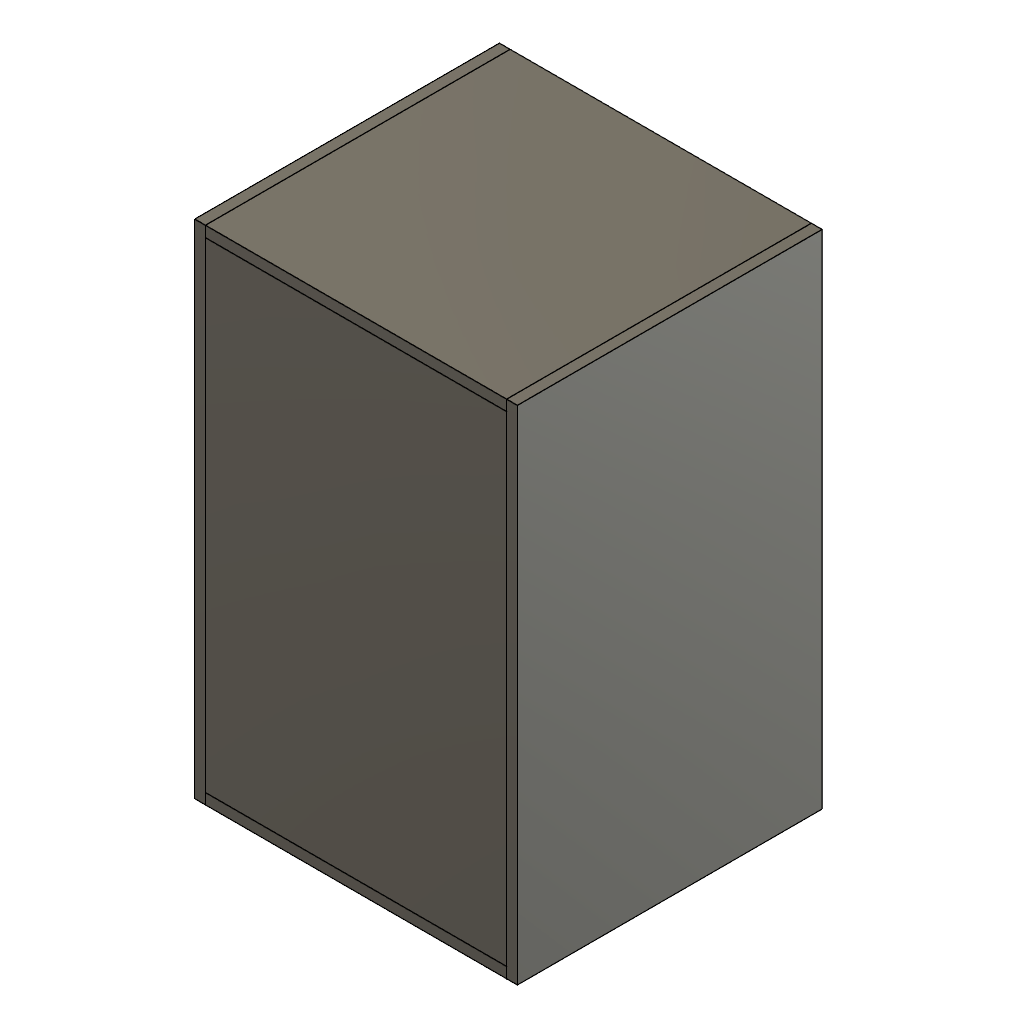
OPEN_LOUD_A0_E08 (Autodesk Fusion 360 design; units mm, degrees)
part number: 2026-11-10-20-48-52-947
part number: 2026-11-10-20-48-53-589
part number: 2026-11-10-20-48-53-740
part number: 2026-11-10-20-48-53-848
part number: 2026-11-10-20-48-53-970
part number: 2026-11-10-20-48-54-126
part number: 2026-11-10-20-48-54-325
part number: 2026-11-10-20-48-55-148
part number: 2026-11-10-20-49-07-626
part number: 2026-11-10-20-49-14-785
part number: 2026-11-10-20-49-16-073
part number: 2026-11-10-20-49-17-374
part number: 2026-11-10-20-49-18-731
part number: 2026-11-10-20-49-20-071
part number: 2026-11-10-20-49-21-540
part number: 2026-11-10-20-49-22-962
part number: 2026-11-10-20-49-24-387
part number: 2026-11-10-20-49-25-757
part number: 2026-11-10-20-49-30-177
part number: 2026-11-10-20-49-35-720
part number: 2026-11-10-20-49-37-012
Autodesk Fusion 360 part; units mm, degrees
(part 1 of 2)
ref_plane "Arbeitsebene1" through (0, 0, 0) normal (0, 0, 1) x (1, 0, 0) in component "Side_left"
sketch "Skizze1" plane through (0, 0, 0) normal (0, 0, 1) x (1, 0, 0) in component "Side_left"
  line L0 (0, 0) -> (12, 0)
  line L1 (12, 0) -> (12, 560)
  line L2 (12, 560) -> (0, 560)
  line L3 (0, 560) -> (0, 0)
  dimension "d76" = 12
  dimension "d77" = 560
  constraint horizontal L0
  constraint horizontal L2
  constraint vertical L1
  constraint vertical L3
  constraint coincident L0.start L3.end
  measures "d76" horizontal distance of L0.start L0.end
  measures "d77" vertical distance of L0.end L1.end
extrude "Side_left" add sketch "Skizze1" along normal blind 340 makes body 1 in component "Side_left"
ref_plane "Arbeitsebene1" through (0, 0, 0) normal (0, 0, 1) x (1, 0, 0) in component "Side_right"
sketch "Skizze1 (2)" plane through (0, 0, 0) normal (0, 0, 1) x (1, 0, 0) in component "Side_right"
  line L0 (348, 0) -> (360, 0)
  line L1 (360, 0) -> (360, 560)
  line L2 (360, 560) -> (348, 560)
  line L3 (348, 560) -> (348, 0)
  dimension "d82" = 348
  dimension "d83" = 12
  dimension "d84" = 560
  constraint horizontal L0
  constraint horizontal L2
  constraint vertical L1
  constraint vertical L3
  constraint horizontal origin L0.start
  measures "d82" horizontal distance of origin L0.start
  measures "d83" horizontal distance of L0.start L0.end
  measures "d84" vertical distance of L0.end L1.end
extrude "Side_right" add sketch "Skizze1 (2)" along normal blind 340 separate body makes body 2 in component "Side_right"
ref_plane "Arbeitsebene1" through (0, 0, 0) normal (0, 0, 1) x (1, 0, 0) in component "Bottom"
sketch "Skizze1 (3)" plane through (0, 0, 0) normal (0, 0, 1) x (1, 0, 0) in component "Bottom"
  line L0 (12, 0) -> (348, 0)
  line L1 (348, 0) -> (348, 12)
  line L2 (348, 12) -> (12, 12)
  line L3 (12, 12) -> (12, 0)
  dimension "d89" = 12
  dimension "d90" = 336
  dimension "d91" = 12
  constraint horizontal L0
  constraint horizontal L2
  constraint vertical L1
  constraint vertical L3
  constraint horizontal origin L0.start
  measures "d89" horizontal distance of origin L0.start
  measures "d90" horizontal distance of L0.start L0.end
  measures "d91" vertical distance of L0.end L1.end
extrude "Bottom" add sketch "Skizze1 (3)" along normal blind 340 separate body makes body 3 in component "Bottom"
ref_plane "Arbeitsebene1" through (0, 0, 0) normal (0, 0, 1) x (1, 0, 0) in component "Top"
sketch "Skizze1 (4)" plane through (0, 0, 0) normal (0, 0, 1) x (1, 0, 0) in component "Top"
  line L0 (12, 548) -> (348, 548)
  line L1 (348, 548) -> (348, 560)
  line L2 (348, 560) -> (12, 560)
  line L3 (12, 560) -> (12, 548)
  dimension "d96" = 12
  dimension "d97" = 548
  dimension "d98" = 336
  dimension "d99" = 12
  constraint horizontal L0
  constraint horizontal L2
  constraint vertical L1
  constraint vertical L3
  measures "d96" horizontal distance of origin L0.start
  measures "d97" vertical distance of origin L0.start
  measures "d98" horizontal distance of L0.start L0.end
  measures "d99" vertical distance of L0.end L1.end
extrude "Top" add sketch "Skizze1 (4)" along normal blind 340 separate body makes body 4 in component "Top"
ref_plane "Arbeitsebene1" through (0, 0, 0) normal (0, 0, 1) x (1, 0, 0) in component "Baffle"
sketch "Skizze1 (5)" plane through (0, 0, 0) normal (0, 0, 1) x (1, 0, 0) in component "Baffle"
  line L0 (12, 12) -> (348, 12)
  line L1 (348, 12) -> (348, 548)
  line L2 (348, 548) -> (12, 548)
  line L3 (12, 548) -> (12, 12)
  dimension "d104" = 12
  dimension "d105" = 12
  dimension "d106" = 336
  dimension "d107" = 536
  constraint horizontal L0
  constraint horizontal L2
  constraint vertical L1
  constraint vertical L3
  measures "d104" horizontal distance of origin L0.start
  measures "d105" vertical distance of origin L0.start
  measures "d106" horizontal distance of L0.start L0.end
  measures "d107" vertical distance of L0.end L1.end
extrude "Baffle" add sketch "Skizze1 (5)" along normal blind 12 separate body makes body 5 in component "Baffle"
ref_plane "Arbeitsebene1" through (0, 0, 328) normal (0, 0, 1) x (1, 0, 0) in component "Rear_removable"
sketch "Skizze1 (6)" plane through (0, 0, 328) normal (0, 0, 1) x (1, 0, 0) in component "Rear_removable"
  line L0 (12, 12) -> (348, 12)
  line L1 (348, 12) -> (348, 548)
  line L2 (348, 548) -> (12, 548)
  line L3 (12, 548) -> (12, 12)
  dimension "d112" = 12
  dimension "d113" = 12
  dimension "d114" = 336
  dimension "d115" = 536
  constraint horizontal L0
  constraint horizontal L2
  constraint vertical L1
  constraint vertical L3
  measures "d112" horizontal distance of origin L0.start
  measures "d113" vertical distance of origin L0.start
  measures "d114" horizontal distance of L0.start L0.end
  measures "d115" vertical distance of L0.end L1.end
extrude "Rear_removable" add sketch "Skizze1 (6)" along normal blind 12 separate body makes body 6 in component "Rear_removable"
ref_plane "Arbeitsebene2" through (0, 0, 0) normal (0, 0, 1) x (1, 0, 0) in component "Baffle"
sketch "Skizze2" plane through (0, 0, 0) normal (0, 0, 1) x (1, 0, 0) in component "Baffle"
  circle A0 centre (180, 260) radius 117.15
  dimension "d120" = 180
  dimension "d121" = 260
  dimension "d122" = 234.3
  measures "d120" horizontal distance of origin A0.centre
  measures "d121" vertical distance of origin A0.centre
  measures "d122" diameter of A0
extrude "LF_cut" cut sketch "Skizze2" along normal blind 12 bodies 5 in component "Baffle"
ref_plane "Arbeitsebene3" through (0, 0, 0) normal (0, 0, 1) x (1, 0, 0) in component "Baffle"
sketch "Skizze3" plane through (0, 0, 0) normal (0, 0, 1) x (1, 0, 0) in component "Baffle"
  circle A0 centre (80, 82) radius 48.9864
  dimension "d127" = 80
  dimension "d128" = 82
  dimension "d129" = 97.9728
  measures "d127" horizontal distance of origin A0.centre
  measures "d128" vertical distance of origin A0.centre
  measures "d129" diameter of A0
extrude "Port_cut" cut sketch "Skizze3" along normal blind 12 bodies 5 in component "Baffle"
ref_plane "Arbeitsebene4" through (0, 0, 0) normal (0, 0, 1) x (1, 0, 0) in component "Baffle"
sketch "Skizze4" plane through (0, 0, 0) normal (0, 0, 1) x (1, 0, 0) in component "Baffle"
  line L0 (128, 418) -> (232, 418)
  line L1 (232, 418) -> (232, 522)
  line L2 (232, 522) -> (128, 522)
  line L3 (128, 522) -> (128, 418)
  dimension "d134" = 128
  dimension "d135" = 418
  dimension "d136" = 104
  dimension "d137" = 104
  constraint horizontal L0
  constraint horizontal L2
  constraint vertical L1
  constraint vertical L3
  measures "d134" horizontal distance of origin L0.start
  measures "d135" vertical distance of origin L0.start
  measures "d136" horizontal distance of L0.start L0.end
  measures "d137" vertical distance of L0.end L1.end
extrude "Horn_cut" cut sketch "Skizze4" along normal blind 12 bodies 5 in component "Baffle"
ref_plane "Arbeitsebene1" through (0, 0, 12) normal (0, 0, 1) x (1, 0, 0) in component "Baffle_inner_lamination"
sketch "Skizze1 (7)" plane through (0, 0, 12) normal (0, 0, 1) x (1, 0, 0) in component "Baffle_inner_lamination"
  line L0 (12, 12) -> (348, 12)
  line L1 (348, 12) -> (348, 548)
  line L2 (348, 548) -> (12, 548)
  line L3 (12, 548) -> (12, 12)
  dimension "d142" = 12
  dimension "d143" = 12
  dimension "d144" = 336
  dimension "d145" = 536
  constraint horizontal L0
  constraint horizontal L2
  constraint vertical L1
  constraint vertical L3
  measures "d142" horizontal distance of origin L0.start
  measures "d143" vertical distance of origin L0.start
  measures "d144" horizontal distance of L0.start L0.end
  measures "d145" vertical distance of L0.end L1.end
extrude "Baffle_inner_lamination" add sketch "Skizze1 (7)" along normal blind 12 separate body makes body 7 in component "Baffle_inner_lamination"
ref_plane "Arbeitsebene2" through (0, 0, 12) normal (0, 0, 1) x (1, 0, 0) in component "Baffle_inner_lamination"
sketch "Skizze2 (2)" plane through (0, 0, 12) normal (0, 0, 1) x (1, 0, 0) in component "Baffle_inner_lamination"
  circle A0 centre (180, 260) radius 117.15
  dimension "d150" = 180
  dimension "d151" = 260
  dimension "d152" = 234.3
  measures "d150" horizontal distance of origin A0.centre
  measures "d151" vertical distance of origin A0.centre
  measures "d152" diameter of A0
extrude "LF_reinforcement_cut" cut sketch "Skizze2 (2)" along normal blind 12 bodies 7 in component "Baffle_inner_lamination"
ref_plane "Arbeitsebene3" through (0, 0, 12) normal (0, 0, 1) x (1, 0, 0) in component "Baffle_inner_lamination"
sketch "Skizze3 (2)" plane through (0, 0, 12) normal (0, 0, 1) x (1, 0, 0) in component "Baffle_inner_lamination"
  circle A0 centre (80, 82) radius 48.9864
  dimension "d157" = 80
  dimension "d158" = 82
  dimension "d159" = 97.9728
  measures "d157" horizontal distance of origin A0.centre
  measures "d158" vertical distance of origin A0.centre
  measures "d159" diameter of A0
extrude "Port_reinforcement_cut" cut sketch "Skizze3 (2)" along normal blind 12 bodies 7 in component "Baffle_inner_lamination"
ref_plane "Arbeitsebene4" through (0, 0, 12) normal (0, 0, 1) x (1, 0, 0) in component "Baffle_inner_lamination"
sketch "Skizze4 (2)" plane through (0, 0, 12) normal (0, 0, 1) x (1, 0, 0) in component "Baffle_inner_lamination"
  line L0 (128, 418) -> (232, 418)
  line L1 (232, 418) -> (232, 522)
  line L2 (232, 522) -> (128, 522)
  line L3 (128, 522) -> (128, 418)
  dimension "d164" = 128
  dimension "d165" = 418
  dimension "d166" = 104
  dimension "d167" = 104
  constraint horizontal L0
  constraint horizontal L2
  constraint vertical L1
  constraint vertical L3
  measures "d164" horizontal distance of origin L0.start
  measures "d165" vertical distance of origin L0.start
  measures "d166" horizontal distance of L0.start L0.end
  measures "d167" vertical distance of L0.end L1.end
extrude "Horn_reinforcement_cut" cut sketch "Skizze4 (2)" along normal blind 12 bodies 7 in component "Baffle_inner_lamination"
ref_plane "Arbeitsebene5" through (0, 0, 0) normal (0, 0, 1) x (1, 0, 0) in component "Baffle"
sketch "Skizze5" plane through (0, 0, 0) normal (0, 0, 1) x (1, 0, 0) in component "Baffle"
  circle A0 centre (301.9, 260) radius 2.75
  dimension "d172" = 301.9
  dimension "d173" = 260
  dimension "d174" = 5.5
  measures "d172" horizontal distance of origin A0.centre
  measures "d173" vertical distance of origin A0.centre
  measures "d174" diameter of A0
extrude "LF_M5_bore_0" cut sketch "Skizze5" along normal blind 12 bodies 5 in component "Baffle"
ref_plane "Arbeitsebene6" through (0, 0, 0) normal (0, 0, 1) x (1, 0, 0) in component "Baffle"
sketch "Skizze6" plane through (0, 0, 0) normal (0, 0, 1) x (1, 0, 0) in component "Baffle"
  circle A0 centre (266.1963, 346.1963) radius 2.75
  dimension "d179" = 266.1963
  dimension "d180" = 346.1963
  dimension "d181" = 5.5
  measures "d179" horizontal distance of origin A0.centre
  measures "d180" vertical distance of origin A0.centre
  measures "d181" diameter of A0
extrude "LF_M5_bore_1" cut sketch "Skizze6" along normal blind 12 bodies 5 in component "Baffle"
ref_plane "Arbeitsebene7" through (0, 0, 0) normal (0, 0, 1) x (1, 0, 0) in component "Baffle"
sketch "Skizze7" plane through (0, 0, 0) normal (0, 0, 1) x (1, 0, 0) in component "Baffle"
  circle A0 centre (180, 381.9) radius 2.75
  dimension "d186" = 180
  dimension "d187" = 381.9
  dimension "d188" = 5.5
  measures "d186" horizontal distance of origin A0.centre
  measures "d187" vertical distance of origin A0.centre
  measures "d188" diameter of A0
extrude "LF_M5_bore_2" cut sketch "Skizze7" along normal blind 12 bodies 5 in component "Baffle"
ref_plane "Arbeitsebene8" through (0, 0, 0) normal (0, 0, 1) x (1, 0, 0) in component "Baffle"
sketch "Skizze8" plane through (0, 0, 0) normal (0, 0, 1) x (1, 0, 0) in component "Baffle"
  circle A0 centre (93.8037, 346.1963) radius 2.75
  dimension "d193" = 93.8037
  dimension "d194" = 346.1963
  dimension "d195" = 5.5
  measures "d193" horizontal distance of origin A0.centre
  measures "d194" vertical distance of origin A0.centre
  measures "d195" diameter of A0
extrude "LF_M5_bore_3" cut sketch "Skizze8" along normal blind 12 bodies 5 in component "Baffle"
ref_plane "Arbeitsebene9" through (0, 0, 0) normal (0, 0, 1) x (1, 0, 0) in component "Baffle"
sketch "Skizze9" plane through (0, 0, 0) normal (0, 0, 1) x (1, 0, 0) in component "Baffle"
  circle A0 centre (58.1, 260) radius 2.75
  dimension "d200" = 58.1
  dimension "d201" = 260
  dimension "d202" = 5.5
  measures "d200" horizontal distance of origin A0.centre
  measures "d201" vertical distance of origin A0.centre
  measures "d202" diameter of A0
extrude "LF_M5_bore_4" cut sketch "Skizze9" along normal blind 12 bodies 5 in component "Baffle"
ref_plane "Arbeitsebene10" through (0, 0, 0) normal (0, 0, 1) x (1, 0, 0) in component "Baffle"
sketch "Skizze10" plane through (0, 0, 0) normal (0, 0, 1) x (1, 0, 0) in component "Baffle"
  circle A0 centre (93.8037, 173.8037) radius 2.75
  dimension "d207" = 93.8037
  dimension "d208" = 173.8037
  dimension "d209" = 5.5
  measures "d207" horizontal distance of origin A0.centre
  measures "d208" vertical distance of origin A0.centre
  measures "d209" diameter of A0
extrude "LF_M5_bore_5" cut sketch "Skizze10" along normal blind 12 bodies 5 in component "Baffle"
ref_plane "Arbeitsebene11" through (0, 0, 0) normal (0, 0, 1) x (1, 0, 0) in component "Baffle"
sketch "Skizze11" plane through (0, 0, 0) normal (0, 0, 1) x (1, 0, 0) in component "Baffle"
  circle A0 centre (180, 138.1) radius 2.75
  dimension "d214" = 180
  dimension "d215" = 138.1
  dimension "d216" = 5.5
  measures "d214" horizontal distance of origin A0.centre
  measures "d215" vertical distance of origin A0.centre
  measures "d216" diameter of A0
extrude "LF_M5_bore_6" cut sketch "Skizze11" along normal blind 12 bodies 5 in component "Baffle"
ref_plane "Arbeitsebene12" through (0, 0, 0) normal (0, 0, 1) x (1, 0, 0) in component "Baffle"
sketch "Skizze12" plane through (0, 0, 0) normal (0, 0, 1) x (1, 0, 0) in component "Baffle"
  circle A0 centre (266.1963, 173.8037) radius 2.75
  dimension "d221" = 266.1963
  dimension "d222" = 173.8037
  dimension "d223" = 5.5
  measures "d221" horizontal distance of origin A0.centre
  measures "d222" vertical distance of origin A0.centre
  measures "d223" diameter of A0
extrude "LF_M5_bore_7" cut sketch "Skizze12" along normal blind 12 bodies 5 in component "Baffle"
ref_plane "Arbeitsebene13" through (0, 0, 0) normal (0, 0, 1) x (1, 0, 0) in component "Baffle"
sketch "Skizze13" plane through (0, 0, 0) normal (0, 0, 1) x (1, 0, 0) in component "Baffle"
  circle A0 centre (123, 413) radius 2.25
  dimension "d228" = 123
  dimension "d229" = 413
  dimension "d230" = 4.5
  measures "d228" horizontal distance of origin A0.centre
  measures "d229" vertical distance of origin A0.centre
  measures "d230" diameter of A0
extrude "Horn_M4_bore" cut sketch "Skizze13" along normal blind 12 bodies 5 in component "Baffle"
ref_plane "Arbeitsebene14" through (0, 0, 0) normal (0, 0, 1) x (1, 0, 0) in component "Baffle"
sketch "Skizze14" plane through (0, 0, 0) normal (0, 0, 1) x (1, 0, 0) in component "Baffle"
  circle A0 centre (123, 527) radius 2.25
  dimension "d235" = 123
  dimension "d236" = 527
  dimension "d237" = 4.5
  measures "d235" horizontal distance of origin A0.centre
  measures "d236" vertical distance of origin A0.centre
  measures "d237" diameter of A0
extrude "Horn_M4_bore (1)" cut sketch "Skizze14" along normal blind 12 bodies 5 in component "Baffle"
ref_plane "Arbeitsebene15" through (0, 0, 0) normal (0, 0, 1) x (1, 0, 0) in component "Baffle"
sketch "Skizze15" plane through (0, 0, 0) normal (0, 0, 1) x (1, 0, 0) in component "Baffle"
  circle A0 centre (237, 413) radius 2.25
  dimension "d242" = 237
  dimension "d243" = 413
  dimension "d244" = 4.5
  measures "d242" horizontal distance of origin A0.centre
  measures "d243" vertical distance of origin A0.centre
  measures "d244" diameter of A0
extrude "Horn_M4_bore (2)" cut sketch "Skizze15" along normal blind 12 bodies 5 in component "Baffle"
ref_plane "Arbeitsebene16" through (0, 0, 0) normal (0, 0, 1) x (1, 0, 0) in component "Baffle"
sketch "Skizze16" plane through (0, 0, 0) normal (0, 0, 1) x (1, 0, 0) in component "Baffle"
  circle A0 centre (237, 527) radius 2.25
  dimension "d249" = 237
  dimension "d250" = 527
  dimension "d251" = 4.5
  measures "d249" horizontal distance of origin A0.centre
  measures "d250" vertical distance of origin A0.centre
  measures "d251" diameter of A0
extrude "Horn_M4_bore (3)" cut sketch "Skizze16" along normal blind 12 bodies 5 in component "Baffle"
ref_plane "Arbeitsebene5" through (0, 0, 12) normal (0, 0, 1) x (1, 0, 0) in component "Baffle_inner_lamination"
sketch "Skizze5 (2)" plane through (0, 0, 12) normal (0, 0, 1) x (1, 0, 0) in component "Baffle_inner_lamination"
  circle A0 centre (301.9, 260) radius 2.75
  dimension "d256" = 301.9
  dimension "d257" = 260
  dimension "d258" = 5.5
  measures "d256" horizontal distance of origin A0.centre
  measures "d257" vertical distance of origin A0.centre
  measures "d258" diameter of A0
extrude "LF_M5_bore_0'" cut sketch "Skizze5 (2)" along normal blind 12 bodies 7 in component "Baffle_inner_lamination"
ref_plane "Arbeitsebene6" through (0, 0, 12) normal (0, 0, 1) x (1, 0, 0) in component "Baffle_inner_lamination"
sketch "Skizze6 (2)" plane through (0, 0, 12) normal (0, 0, 1) x (1, 0, 0) in component "Baffle_inner_lamination"
  circle A0 centre (266.1963, 346.1963) radius 2.75
  dimension "d263" = 266.1963
  dimension "d264" = 346.1963
  dimension "d265" = 5.5
  measures "d263" horizontal distance of origin A0.centre
  measures "d264" vertical distance of origin A0.centre
  measures "d265" diameter of A0
extrude "LF_M5_bore_1'" cut sketch "Skizze6 (2)" along normal blind 12 bodies 7 in component "Baffle_inner_lamination"
ref_plane "Arbeitsebene7" through (0, 0, 12) normal (0, 0, 1) x (1, 0, 0) in component "Baffle_inner_lamination"
sketch "Skizze7 (2)" plane through (0, 0, 12) normal (0, 0, 1) x (1, 0, 0) in component "Baffle_inner_lamination"
  circle A0 centre (180, 381.9) radius 2.75
  dimension "d270" = 180
  dimension "d271" = 381.9
  dimension "d272" = 5.5
  measures "d270" horizontal distance of origin A0.centre
  measures "d271" vertical distance of origin A0.centre
  measures "d272" diameter of A0
extrude "LF_M5_bore_2'" cut sketch "Skizze7 (2)" along normal blind 12 bodies 7 in component "Baffle_inner_lamination"
ref_plane "Arbeitsebene8" through (0, 0, 12) normal (0, 0, 1) x (1, 0, 0) in component "Baffle_inner_lamination"
sketch "Skizze8 (2)" plane through (0, 0, 12) normal (0, 0, 1) x (1, 0, 0) in component "Baffle_inner_lamination"
  circle A0 centre (93.8037, 346.1963) radius 2.75
  dimension "d277" = 93.8037
  dimension "d278" = 346.1963
  dimension "d279" = 5.5
  measures "d277" horizontal distance of origin A0.centre
  measures "d278" vertical distance of origin A0.centre
  measures "d279" diameter of A0
extrude "LF_M5_bore_3'" cut sketch "Skizze8 (2)" along normal blind 12 bodies 7 in component "Baffle_inner_lamination"
ref_plane "Arbeitsebene9" through (0, 0, 12) normal (0, 0, 1) x (1, 0, 0) in component "Baffle_inner_lamination"
sketch "Skizze9 (2)" plane through (0, 0, 12) normal (0, 0, 1) x (1, 0, 0) in component "Baffle_inner_lamination"
  circle A0 centre (58.1, 260) radius 2.75
  dimension "d284" = 58.1
  dimension "d285" = 260
  dimension "d286" = 5.5
  measures "d284" horizontal distance of origin A0.centre
  measures "d285" vertical distance of origin A0.centre
  measures "d286" diameter of A0
extrude "LF_M5_bore_4'" cut sketch "Skizze9 (2)" along normal blind 12 bodies 7 in component "Baffle_inner_lamination"
ref_plane "Arbeitsebene10" through (0, 0, 12) normal (0, 0, 1) x (1, 0, 0) in component "Baffle_inner_lamination"
sketch "Skizze10 (2)" plane through (0, 0, 12) normal (0, 0, 1) x (1, 0, 0) in component "Baffle_inner_lamination"
  circle A0 centre (93.8037, 173.8037) radius 2.75
  dimension "d291" = 93.8037
  dimension "d292" = 173.8037
  dimension "d293" = 5.5
  measures "d291" horizontal distance of origin A0.centre
  measures "d292" vertical distance of origin A0.centre
  measures "d293" diameter of A0
extrude "LF_M5_bore_5'" cut sketch "Skizze10 (2)" along normal blind 12 bodies 7 in component "Baffle_inner_lamination"
ref_plane "Arbeitsebene11" through (0, 0, 12) normal (0, 0, 1) x (1, 0, 0) in component "Baffle_inner_lamination"
sketch "Skizze11 (2)" plane through (0, 0, 12) normal (0, 0, 1) x (1, 0, 0) in component "Baffle_inner_lamination"
  circle A0 centre (180, 138.1) radius 2.75
  dimension "d298" = 180
  dimension "d299" = 138.1
  dimension "d300" = 5.5
  measures "d298" horizontal distance of origin A0.centre
  measures "d299" vertical distance of origin A0.centre
  measures "d300" diameter of A0
extrude "LF_M5_bore_6'" cut sketch "Skizze11 (2)" along normal blind 12 bodies 7 in component "Baffle_inner_lamination"
ref_plane "Arbeitsebene12" through (0, 0, 12) normal (0, 0, 1) x (1, 0, 0) in component "Baffle_inner_lamination"
sketch "Skizze12 (2)" plane through (0, 0, 12) normal (0, 0, 1) x (1, 0, 0) in component "Baffle_inner_lamination"
  circle A0 centre (266.1963, 173.8037) radius 2.75
  dimension "d305" = 266.1963
  dimension "d306" = 173.8037
  dimension "d307" = 5.5
  measures "d305" horizontal distance of origin A0.centre
  measures "d306" vertical distance of origin A0.centre
  measures "d307" diameter of A0
extrude "LF_M5_bore_7'" cut sketch "Skizze12 (2)" along normal blind 12 bodies 7 in component "Baffle_inner_lamination"
ref_plane "Arbeitsebene13" through (0, 0, 12) normal (0, 0, 1) x (1, 0, 0) in component "Baffle_inner_lamination"
sketch "Skizze13 (2)" plane through (0, 0, 12) normal (0, 0, 1) x (1, 0, 0) in component "Baffle_inner_lamination"
  circle A0 centre (123, 413) radius 2.25
  dimension "d312" = 123
  dimension "d313" = 413
  dimension "d314" = 4.5
  measures "d312" horizontal distance of origin A0.centre
  measures "d313" vertical distance of origin A0.centre
  measures "d314" diameter of A0
extrude "Horn_M4_bore'" cut sketch "Skizze13 (2)" along normal blind 12 bodies 7 in component "Baffle_inner_lamination"
ref_plane "Arbeitsebene14" through (0, 0, 12) normal (0, 0, 1) x (1, 0, 0) in component "Baffle_inner_lamination"
sketch "Skizze14 (2)" plane through (0, 0, 12) normal (0, 0, 1) x (1, 0, 0) in component "Baffle_inner_lamination"
  circle A0 centre (123, 527) radius 2.25
  dimension "d319" = 123
  dimension "d320" = 527
  dimension "d321" = 4.5
  measures "d319" horizontal distance of origin A0.centre
  measures "d320" vertical distance of origin A0.centre
  measures "d321" diameter of A0
extrude "Horn_M4_bore (1)'" cut sketch "Skizze14 (2)" along normal blind 12 bodies 7 in component "Baffle_inner_lamination"
ref_plane "Arbeitsebene15" through (0, 0, 12) normal (0, 0, 1) x (1, 0, 0) in component "Baffle_inner_lamination"
sketch "Skizze15 (2)" plane through (0, 0, 12) normal (0, 0, 1) x (1, 0, 0) in component "Baffle_inner_lamination"
  circle A0 centre (237, 413) radius 2.25
  dimension "d326" = 237
  dimension "d327" = 413
  dimension "d328" = 4.5
  measures "d326" horizontal distance of origin A0.centre
  measures "d327" vertical distance of origin A0.centre
  measures "d328" diameter of A0
extrude "Horn_M4_bore (2)'" cut sketch "Skizze15 (2)" along normal blind 12 bodies 7 in component "Baffle_inner_lamination"
ref_plane "Arbeitsebene16" through (0, 0, 12) normal (0, 0, 1) x (1, 0, 0) in component "Baffle_inner_lamination"
sketch "Skizze16 (2)" plane through (0, 0, 12) normal (0, 0, 1) x (1, 0, 0) in component "Baffle_inner_lamination"
  circle A0 centre (237, 527) radius 2.25
  dimension "d333" = 237
  dimension "d334" = 527
  dimension "d335" = 4.5
  measures "d333" horizontal distance of origin A0.centre
  measures "d334" vertical distance of origin A0.centre
  measures "d335" diameter of A0
extrude "Horn_M4_bore (3)'" cut sketch "Skizze16 (2)" along normal blind 12 bodies 7 in component "Baffle_inner_lamination"
ref_plane "Arbeitsebene1" through (0, 0, 24) normal (0, 0, 1) x (1, 0, 0) in component "LF_steel_backing_ring_candidate"
sketch "Skizze1 (8)" plane through (0, 0, 24) normal (0, 0, 1) x (1, 0, 0) in component "LF_steel_backing_ring_candidate"
  circle A0 centre (180, 260) radius 140
  circle A1 centre (180, 260) radius 110
  dimension "d340" = 180
  dimension "d341" = 260
  dimension "d342" = 280
  dimension "d343" = 220
  constraint concentric A0 A1
  measures "d340" horizontal distance of origin A0.centre
  measures "d341" vertical distance of origin A0.centre
  measures "d342" diameter of A0
  measures "d343" diameter of A1
extrude "Steel_backing_ring" add sketch "Skizze1 (8)" along normal blind 3 separate body makes body 8 in component "LF_steel_backing_ring_candidate"
ref_plane "Arbeitsebene2" through (0, 0, 24) normal (0, 0, 1) x (1, 0, 0) in component "LF_steel_backing_ring_candidate"
sketch "Skizze2 (3)" plane through (0, 0, 24) normal (0, 0, 1) x (1, 0, 0) in component "LF_steel_backing_ring_candidate"
  circle A0 centre (301.9, 260) radius 2.75
  dimension "d348" = 301.9
  dimension "d349" = 260
  dimension "d350" = 5.5
  measures "d348" horizontal distance of origin A0.centre
  measures "d349" vertical distance of origin A0.centre
  measures "d350" diameter of A0
extrude "Steel_M5_bore_0" cut sketch "Skizze2 (3)" along normal blind 3 bodies 8 in component "LF_steel_backing_ring_candidate"
ref_plane "Arbeitsebene3" through (0, 0, 24) normal (0, 0, 1) x (1, 0, 0) in component "LF_steel_backing_ring_candidate"
sketch "Skizze3 (3)" plane through (0, 0, 24) normal (0, 0, 1) x (1, 0, 0) in component "LF_steel_backing_ring_candidate"
  circle A0 centre (266.1963, 346.1963) radius 2.75
  dimension "d355" = 266.1963
  dimension "d356" = 346.1963
  dimension "d357" = 5.5
  measures "d355" horizontal distance of origin A0.centre
  measures "d356" vertical distance of origin A0.centre
  measures "d357" diameter of A0
extrude "Steel_M5_bore_1" cut sketch "Skizze3 (3)" along normal blind 3 bodies 8 in component "LF_steel_backing_ring_candidate"
ref_plane "Arbeitsebene4" through (0, 0, 24) normal (0, 0, 1) x (1, 0, 0) in component "LF_steel_backing_ring_candidate"
sketch "Skizze4 (3)" plane through (0, 0, 24) normal (0, 0, 1) x (1, 0, 0) in component "LF_steel_backing_ring_candidate"
  circle A0 centre (180, 381.9) radius 2.75
  dimension "d362" = 180
  dimension "d363" = 381.9
  dimension "d364" = 5.5
  measures "d362" horizontal distance of origin A0.centre
  measures "d363" vertical distance of origin A0.centre
  measures "d364" diameter of A0
extrude "Steel_M5_bore_2" cut sketch "Skizze4 (3)" along normal blind 3 bodies 8 in component "LF_steel_backing_ring_candidate"
ref_plane "Arbeitsebene5" through (0, 0, 24) normal (0, 0, 1) x (1, 0, 0) in component "LF_steel_backing_ring_candidate"
sketch "Skizze5 (3)" plane through (0, 0, 24) normal (0, 0, 1) x (1, 0, 0) in component "LF_steel_backing_ring_candidate"
  circle A0 centre (93.8037, 346.1963) radius 2.75
  dimension "d369" = 93.8037
  dimension "d370" = 346.1963
  dimension "d371" = 5.5
  measures "d369" horizontal distance of origin A0.centre
  measures "d370" vertical distance of origin A0.centre
  measures "d371" diameter of A0
extrude "Steel_M5_bore_3" cut sketch "Skizze5 (3)" along normal blind 3 bodies 8 in component "LF_steel_backing_ring_candidate"
ref_plane "Arbeitsebene6" through (0, 0, 24) normal (0, 0, 1) x (1, 0, 0) in component "LF_steel_backing_ring_candidate"
sketch "Skizze6 (3)" plane through (0, 0, 24) normal (0, 0, 1) x (1, 0, 0) in component "LF_steel_backing_ring_candidate"
  circle A0 centre (58.1, 260) radius 2.75
  dimension "d376" = 58.1
  dimension "d377" = 260
  dimension "d378" = 5.5
  measures "d376" horizontal distance of origin A0.centre
  measures "d377" vertical distance of origin A0.centre
  measures "d378" diameter of A0
extrude "Steel_M5_bore_4" cut sketch "Skizze6 (3)" along normal blind 3 bodies 8 in component "LF_steel_backing_ring_candidate"
ref_plane "Arbeitsebene7" through (0, 0, 24) normal (0, 0, 1) x (1, 0, 0) in component "LF_steel_backing_ring_candidate"
sketch "Skizze7 (3)" plane through (0, 0, 24) normal (0, 0, 1) x (1, 0, 0) in component "LF_steel_backing_ring_candidate"
  circle A0 centre (93.8037, 173.8037) radius 2.75
  dimension "d383" = 93.8037
  dimension "d384" = 173.8037
  dimension "d385" = 5.5
  measures "d383" horizontal distance of origin A0.centre
  measures "d384" vertical distance of origin A0.centre
  measures "d385" diameter of A0
extrude "Steel_M5_bore_5" cut sketch "Skizze7 (3)" along normal blind 3 bodies 8 in component "LF_steel_backing_ring_candidate"
ref_plane "Arbeitsebene8" through (0, 0, 24) normal (0, 0, 1) x (1, 0, 0) in component "LF_steel_backing_ring_candidate"
sketch "Skizze8 (3)" plane through (0, 0, 24) normal (0, 0, 1) x (1, 0, 0) in component "LF_steel_backing_ring_candidate"
  circle A0 centre (180, 138.1) radius 2.75
  dimension "d390" = 180
  dimension "d391" = 138.1
  dimension "d392" = 5.5
  measures "d390" horizontal distance of origin A0.centre
  measures "d391" vertical distance of origin A0.centre
  measures "d392" diameter of A0
extrude "Steel_M5_bore_6" cut sketch "Skizze8 (3)" along normal blind 3 bodies 8 in component "LF_steel_backing_ring_candidate"
ref_plane "Arbeitsebene9" through (0, 0, 24) normal (0, 0, 1) x (1, 0, 0) in component "LF_steel_backing_ring_candidate"
sketch "Skizze9 (3)" plane through (0, 0, 24) normal (0, 0, 1) x (1, 0, 0) in component "LF_steel_backing_ring_candidate"
  circle A0 centre (266.1963, 173.8037) radius 2.75
  dimension "d397" = 266.1963
  dimension "d398" = 173.8037
  dimension "d399" = 5.5
  measures "d397" horizontal distance of origin A0.centre
  measures "d398" vertical distance of origin A0.centre
  measures "d399" diameter of A0
extrude "Steel_M5_bore_7" cut sketch "Skizze9 (3)" along normal blind 3 bodies 8 in component "LF_steel_backing_ring_candidate"
ref_plane "Arbeitsebene1" through (0, 0, 308) normal (0, 0, 1) x (1, 0, 0) in component "Rear_cleat_left"
sketch "Skizze1 (9)" plane through (0, 0, 308) normal (0, 0, 1) x (1, 0, 0) in component "Rear_cleat_left"
  line L0 (12, 12) -> (32, 12)
  line L1 (32, 12) -> (32, 548)
  line L2 (32, 548) -> (12, 548)
  line L3 (12, 548) -> (12, 12)
  dimension "d404" = 12
  dimension "d405" = 12
  dimension "d406" = 20
  dimension "d407" = 536
  constraint horizontal L0
  constraint horizontal L2
  constraint vertical L1
  constraint vertical L3
  measures "d404" horizontal distance of origin L0.start
  measures "d405" vertical distance of origin L0.start
  measures "d406" horizontal distance of L0.start L0.end
  measures "d407" vertical distance of L0.end L1.end
extrude "Rear_cleat_left" add sketch "Skizze1 (9)" along normal blind 20 separate body makes body 9 in component "Rear_cleat_left"
ref_plane "Arbeitsebene1" through (0, 0, 308) normal (0, 0, 1) x (1, 0, 0) in component "Rear_cleat_right"
sketch "Skizze1 (10)" plane through (0, 0, 308) normal (0, 0, 1) x (1, 0, 0) in component "Rear_cleat_right"
  line L0 (328, 12) -> (348, 12)
  line L1 (348, 12) -> (348, 548)
  line L2 (348, 548) -> (328, 548)
  line L3 (328, 548) -> (328, 12)
  dimension "d412" = 328
  dimension "d413" = 12
  dimension "d414" = 20
  dimension "d415" = 536
  constraint horizontal L0
  constraint horizontal L2
  constraint vertical L1
  constraint vertical L3
  measures "d412" horizontal distance of origin L0.start
  measures "d413" vertical distance of origin L0.start
  measures "d414" horizontal distance of L0.start L0.end
  measures "d415" vertical distance of L0.end L1.end
extrude "Rear_cleat_right" add sketch "Skizze1 (10)" along normal blind 20 separate body makes body 10 in component "Rear_cleat_right"
ref_plane "Arbeitsebene1" through (0, 0, 308) normal (0, 0, 1) x (1, 0, 0) in component "Rear_cleat_bottom"
sketch "Skizze1 (11)" plane through (0, 0, 308) normal (0, 0, 1) x (1, 0, 0) in component "Rear_cleat_bottom"
  line L0 (32, 12) -> (328, 12)
  line L1 (328, 12) -> (328, 32)
  line L2 (328, 32) -> (32, 32)
  line L3 (32, 32) -> (32, 12)
  dimension "d420" = 32
  dimension "d421" = 12
  dimension "d422" = 296
  dimension "d423" = 20
  constraint horizontal L0
  constraint horizontal L2
  constraint vertical L1
  constraint vertical L3
  measures "d420" horizontal distance of origin L0.start
  measures "d421" vertical distance of origin L0.start
  measures "d422" horizontal distance of L0.start L0.end
  measures "d423" vertical distance of L0.end L1.end
extrude "Rear_cleat_bottom" add sketch "Skizze1 (11)" along normal blind 20 separate body makes body 11 in component "Rear_cleat_bottom"
ref_plane "Arbeitsebene1" through (0, 0, 308) normal (0, 0, 1) x (1, 0, 0) in component "Rear_cleat_top"
sketch "Skizze1 (12)" plane through (0, 0, 308) normal (0, 0, 1) x (1, 0, 0) in component "Rear_cleat_top"
  line L0 (32, 528) -> (328, 528)
  line L1 (328, 528) -> (328, 548)
  line L2 (328, 548) -> (32, 548)
  line L3 (32, 548) -> (32, 528)
  dimension "d428" = 32
  dimension "d429" = 528
  dimension "d430" = 296
  dimension "d431" = 20
  constraint horizontal L0
  constraint horizontal L2
  constraint vertical L1
  constraint vertical L3
  measures "d428" horizontal distance of origin L0.start
  measures "d429" vertical distance of origin L0.start
  measures "d430" horizontal distance of L0.start L0.end
  measures "d431" vertical distance of L0.end L1.end
extrude "Rear_cleat_top" add sketch "Skizze1 (12)" along normal blind 20 separate body makes body 12 in component "Rear_cleat_top"
ref_plane "Arbeitsebene1" through (0, 0, 165.3579) normal (0, 0, 1) x (1, 0, 0) in component "Service_partition"
sketch "Skizze1 (13)" plane through (0, 0, 165.3579) normal (0, 0, 1) x (1, 0, 0) in component "Service_partition"
  line L0 (12, 342) -> (348, 342)
  line L1 (348, 342) -> (348, 548)
  line L2 (348, 548) -> (12, 548)
  line L3 (12, 548) -> (12, 342)
  dimension "d436" = 12
  dimension "d437" = 342
  dimension "d438" = 336
  dimension "d439" = 206
  constraint horizontal L0
  constraint horizontal L2
  constraint vertical L1
  constraint vertical L3
  measures "d436" horizontal distance of origin L0.start
  measures "d437" vertical distance of origin L0.start
  measures "d438" horizontal distance of L0.start L0.end
  measures "d439" vertical distance of L0.end L1.end
extrude "Service_partition" add sketch "Skizze1 (13)" along normal blind 12 separate body makes body 13 in component "Service_partition"
ref_plane "Arbeitsebene1" through (0, 0, 165.3579) normal (0, 0, 1) x (1, 0, 0) in component "Service_floor"
sketch "Skizze1 (14)" plane through (0, 0, 165.3579) normal (0, 0, 1) x (1, 0, 0) in component "Service_floor"
  line L0 (12, 330) -> (348, 330)
  line L1 (348, 330) -> (348, 342)
  line L2 (348, 342) -> (12, 342)
  line L3 (12, 342) -> (12, 330)
  dimension "d444" = 12
  dimension "d445" = 330
  dimension "d446" = 336
  dimension "d447" = 12
  constraint horizontal L0
  constraint horizontal L2
  constraint vertical L1
  constraint vertical L3
  measures "d444" horizontal distance of origin L0.start
  measures "d445" vertical distance of origin L0.start
  measures "d446" horizontal distance of L0.start L0.end
  measures "d447" vertical distance of L0.end L1.end
extrude "Service_floor" add sketch "Skizze1 (14)" along normal blind 162.6421 separate body makes body 14 in component "Service_floor"
ref_plane "Arbeitsebene1" through (0, 0, 200) normal (0, 0, 1) x (1, 0, 0) in component "Brace_lower"
sketch "Skizze1 (15)" plane through (0, 0, 200) normal (0, 0, 1) x (1, 0, 0) in component "Brace_lower"
  line L0 (12, 240) -> (348, 240)
  line L1 (348, 240) -> (348, 260)
  line L2 (348, 260) -> (12, 260)
  line L3 (12, 260) -> (12, 240)
  dimension "d452" = 12
  dimension "d453" = 240
  dimension "d454" = 336
  dimension "d455" = 20
  constraint horizontal L0
  constraint horizontal L2
  constraint vertical L1
  constraint vertical L3
  measures "d452" horizontal distance of origin L0.start
  measures "d453" vertical distance of origin L0.start
  measures "d454" horizontal distance of L0.start L0.end
  measures "d455" vertical distance of L0.end L1.end
extrude "Brace_lower" add sketch "Skizze1 (15)" along normal blind 12 separate body makes body 15 in component "Brace_lower"
ref_plane "Arbeitsebene1" through (0, 0, 0) normal (0, 0, 1) x (1, 0, 0) in component "Port_round_candidate"
sketch "Skizze1 (16)" plane through (0, 0, 0) normal (0, 0, 1) x (1, 0, 0) in component "Port_round_candidate"
  circle A0 centre (80, 82) radius 48.4864
  circle A1 centre (80, 82) radius 45.4864
  dimension "d460" = 80
  dimension "d461" = 82
  dimension "d462" = 96.9728
  dimension "d463" = 90.9728
  constraint concentric A0 A1
  measures "d460" horizontal distance of origin A0.centre
  measures "d461" vertical distance of origin A0.centre
  measures "d462" diameter of A0
  measures "d463" diameter of A1
extrude "Port_tube" add sketch "Skizze1 (16)" along normal blind 161.4786 separate body makes body 16 in component "Port_round_candidate"
ref_plane "Arbeitsebene1" through (0, 0, -8) normal (0, 0, 1) x (1, 0, 0) in component "REF_Faital_10FE200_4ohm_DATASHEET_ENVELOPE"
sketch "Skizze1 (17)" plane through (0, 0, -8) normal (0, 0, 1) x (1, 0, 0) in component "REF_Faital_10FE200_4ohm_DATASHEET_ENVELOPE"
  circle A0 centre (180, 260) radius 128.4
  circle A1 centre (180, 260) radius 116.65
  dimension "d468" = 180
  dimension "d469" = 260
  dimension "d470" = 256.8
  dimension "d471" = 233.3
  constraint concentric A0 A1
  measures "d468" horizontal distance of origin A0.centre
  measures "d469" vertical distance of origin A0.centre
  measures "d470" diameter of A0
  measures "d471" diameter of A1
extrude "LF_flange_envelope" add sketch "Skizze1 (17)" along normal blind 8 separate body makes body 17 in component "REF_Faital_10FE200_4ohm_DATASHEET_ENVELOPE"
ref_plane "Arbeitsebene2" through (0, 0, 0) normal (0, 0, 1) x (1, 0, 0) in component "REF_Faital_10FE200_4ohm_DATASHEET_ENVELOPE"
sketch "Skizze2 (4)" plane through (0, 0, 0) normal (0, 0, 1) x (1, 0, 0) in component "REF_Faital_10FE200_4ohm_DATASHEET_ENVELOPE"
  circle A0 centre (180, 260) radius 115.9
  dimension "d476" = 180
  dimension "d477" = 260
  dimension "d478" = 231.8
  measures "d476" horizontal distance of origin A0.centre
  measures "d477" vertical distance of origin A0.centre
  measures "d478" diameter of A0
ref_plane "Arbeitsebene3" through (0, 0, 59.3) normal (0, 0, 1) x (1, 0, 0) in component "REF_Faital_10FE200_4ohm_DATASHEET_ENVELOPE"
sketch "Skizze3 (4)" plane through (0, 0, 59.3) normal (0, 0, 1) x (1, 0, 0) in component "REF_Faital_10FE200_4ohm_DATASHEET_ENVELOPE"
  circle A0 centre (180, 260) radius 57.65
  dimension "d481" = 180
  dimension "d482" = 260
  dimension "d483" = 115.3
  measures "d481" horizontal distance of origin A0.centre
  measures "d482" vertical distance of origin A0.centre
  measures "d483" diameter of A0
loft "Basket_clearance_frustum_NOT_SOLID_MATERIAL" add profiles "Skizze2 (4)", "Skizze3 (4)" section 1 section 2 separate body makes body 18 in component "REF_Faital_10FE200_4ohm_DATASHEET_ENVELOPE"
ref_plane "Arbeitsebene4" through (0, 0, 59.3) normal (0, 0, 1) x (1, 0, 0) in component "REF_Faital_10FE200_4ohm_DATASHEET_ENVELOPE"
sketch "Skizze4 (4)" plane through (0, 0, 59.3) normal (0, 0, 1) x (1, 0, 0) in component "REF_Faital_10FE200_4ohm_DATASHEET_ENVELOPE"
  circle A0 centre (180, 260) radius 57.65
  dimension "d486" = 180
  dimension "d487" = 260
  dimension "d488" = 115.3
  measures "d486" horizontal distance of origin A0.centre
  measures "d487" vertical distance of origin A0.centre
  measures "d488" diameter of A0
extrude "Magnet_envelope" add sketch "Skizze4 (4)" along normal blind 34.7 separate body makes body 19 in component "REF_Faital_10FE200_4ohm_DATASHEET_ENVELOPE"
ref_plane "Arbeitsebene1" through (0, 0, -5.5) normal (0, 0, 1) x (1, 0, 0) in component "REF_BC_ME10V3_DATASHEET_ENVELOPE"
sketch "Skizze1 (18)" plane through (0, 0, -5.5) normal (0, 0, 1) x (1, 0, 0) in component "REF_BC_ME10V3_DATASHEET_ENVELOPE"
  line L0 (114.75, 404.75) -> (245.25, 404.75)
  line L1 (245.25, 404.75) -> (245.25, 535.25)
  line L2 (245.25, 535.25) -> (114.75, 535.25)
  line L3 (114.75, 535.25) -> (114.75, 404.75)
  dimension "d493" = 114.75
  dimension "d494" = 404.75
  dimension "d495" = 130.5
  dimension "d496" = 130.5
  constraint horizontal L0
  constraint horizontal L2
  constraint vertical L1
  constraint vertical L3
  measures "d493" horizontal distance of origin L0.start
  measures "d494" vertical distance of origin L0.start
  measures "d495" horizontal distance of L0.start L0.end
  measures "d496" vertical distance of L0.end L1.end
extrude "Horn_flange_envelope" add sketch "Skizze1 (18)" along normal blind 5.5 separate body makes body 20 in component "REF_BC_ME10V3_DATASHEET_ENVELOPE"
ref_plane "Arbeitsebene2" through (0, 0, -5.5) normal (0, 0, 1) x (1, 0, 0) in component "REF_BC_ME10V3_DATASHEET_ENVELOPE"
sketch "Skizze2 (5)" plane through (0, 0, -5.5) normal (0, 0, 1) x (1, 0, 0) in component "REF_BC_ME10V3_DATASHEET_ENVELOPE"
  line L0 (128, 418) -> (232, 418)
  line L1 (232, 418) -> (232, 522)
  line L2 (232, 522) -> (128, 522)
  line L3 (128, 522) -> (128, 418)
  dimension "d501" = 128
  dimension "d502" = 418
  dimension "d503" = 104
  dimension "d504" = 104
  constraint horizontal L0
  constraint horizontal L2
  constraint vertical L1
  constraint vertical L3
  measures "d501" horizontal distance of origin L0.start
  measures "d502" vertical distance of origin L0.start
  measures "d503" horizontal distance of L0.start L0.end
  measures "d504" vertical distance of L0.end L1.end
extrude "Horn_mouth_open" cut sketch "Skizze2 (5)" along normal blind 5.5 bodies 20 in component "REF_BC_ME10V3_DATASHEET_ENVELOPE"
ref_plane "Arbeitsebene3" through (0, 0, 0) normal (0, 0, 1) x (1, 0, 0) in component "REF_BC_ME10V3_DATASHEET_ENVELOPE"
sketch "Skizze3 (5)" plane through (0, 0, 0) normal (0, 0, 1) x (1, 0, 0) in component "REF_BC_ME10V3_DATASHEET_ENVELOPE"
  line L0 (128, 418) -> (232, 418)
  line L1 (232, 418) -> (232, 522)
  line L2 (232, 522) -> (128, 522)
  line L3 (128, 522) -> (128, 418)
  dimension "d509" = 128
  dimension "d510" = 418
  dimension "d511" = 104
  dimension "d512" = 104
  constraint horizontal L0
  constraint horizontal L2
  constraint vertical L1
  constraint vertical L3
  measures "d509" horizontal distance of origin L0.start
  measures "d510" vertical distance of origin L0.start
  measures "d511" horizontal distance of L0.start L0.end
  measures "d512" vertical distance of L0.end L1.end
ref_plane "Arbeitsebene4" through (0, 0, 84.5) normal (0, 0, 1) x (1, 0, 0) in component "REF_BC_ME10V3_DATASHEET_ENVELOPE"
sketch "Skizze4 (5)" plane through (0, 0, 84.5) normal (0, 0, 1) x (1, 0, 0) in component "REF_BC_ME10V3_DATASHEET_ENVELOPE"
  circle A0 centre (180, 470) radius 12.5
  dimension "d515" = 180
  dimension "d516" = 470
  dimension "d517" = 25
  measures "d515" horizontal distance of origin A0.centre
  measures "d516" vertical distance of origin A0.centre
  measures "d517" diameter of A0
loft "Flare_clearance_ONLY_not_acoustic_surface" add profiles "Skizze3 (5)", "Skizze4 (5)" section 1 section 2 separate body makes body 21 in component "REF_BC_ME10V3_DATASHEET_ENVELOPE"
ref_plane "Arbeitsebene1" through (0, 0, 84.5) normal (0, 0, 1) x (1, 0, 0) in component "REF_BC_DE10_DATASHEET_ENVELOPE"
sketch "Skizze1 (19)" plane through (0, 0, 84.5) normal (0, 0, 1) x (1, 0, 0) in component "REF_BC_DE10_DATASHEET_ENVELOPE"
  circle A0 centre (180, 470) radius 45
  dimension "d520" = 180
  dimension "d521" = 470
  dimension "d522" = 90
  measures "d520" horizontal distance of origin A0.centre
  measures "d521" vertical distance of origin A0.centre
  measures "d522" diameter of A0
extrude "DE10_cylinder_envelope" add sketch "Skizze1 (19)" along normal blind 53 separate body makes body 22 in component "REF_BC_DE10_DATASHEET_ENVELOPE"
ref_plane "Arbeitsebene1" through (0, 0, 187.3579) normal (0, 0, 1) x (1, 0, 0) in component "RESERVE_amp_wiring_UNVERIFIED_no_mounting_holes"
sketch "Skizze1 (20)" plane through (0, 0, 187.3579) normal (0, 0, 1) x (1, 0, 0) in component "RESERVE_amp_wiring_UNVERIFIED_no_mounting_holes"
  line L0 (125, 352) -> (235, 352)
  line L1 (235, 352) -> (235, 462)
  line L2 (235, 462) -> (125, 462)
  line L3 (125, 462) -> (125, 352)
  dimension "d527" = 125
  dimension "d528" = 352
  dimension "d529" = 110
  dimension "d530" = 110
  constraint horizontal L0
  constraint horizontal L2
  constraint vertical L1
  constraint vertical L3
  measures "d527" horizontal distance of origin L0.start
  measures "d528" vertical distance of origin L0.start
  measures "d529" horizontal distance of L0.start L0.end
  measures "d530" vertical distance of L0.end L1.end
extrude "Amp_space_reserve" add sketch "Skizze1 (20)" along normal blind 40 separate body makes body 23 in component "RESERVE_amp_wiring_UNVERIFIED_no_mounting_holes"
component "Side_left" placed x (1, 0, 0) y (0, 1, 0) z (0, 0, 1) at (0, 0, 0)
component "Side_right" placed x (1, 0, 0) y (0, 1, 0) z (0, 0, 1) at (0, 0, 0)
component "Bottom" placed x (1, 0, 0) y (0, 1, 0) z (0, 0, 1) at (0, 0, 0)
component "Top" placed x (1, 0, 0) y (0, 1, 0) z (0, 0, 1) at (0, 0, 0)
component "Baffle" placed x (1, 0, 0) y (0, 1, 0) z (0, 0, 1) at (0, 0, 0)
component "Rear_removable" placed x (1, 0, 0) y (0, 1, 0) z (0, 0, 1) at (0, 0, 0)
component "Baffle_inner_lamination" placed x (1, 0, 0) y (0, 1, 0) z (0, 0, 1) at (0, 0, 0)
component "LF_steel_backing_ring_candidate" placed x (1, 0, 0) y (0, 1, 0) z (0, 0, 1) at (0, 0, 0)
component "Rear_cleat_left" placed x (1, 0, 0) y (0, 1, 0) z (0, 0, 1) at (0, 0, 0)
component "Rear_cleat_right" placed x (1, 0, 0) y (0, 1, 0) z (0, 0, 1) at (0, 0, 0)
component "Rear_cleat_bottom" placed x (1, 0, 0) y (0, 1, 0) z (0, 0, 1) at (0, 0, 0)
component "Rear_cleat_top" placed x (1, 0, 0) y (0, 1, 0) z (0, 0, 1) at (0, 0, 0)
component "Service_partition" placed x (1, 0, 0) y (0, 1, 0) z (0, 0, 1) at (0, 0, 0)
component "Service_floor" placed x (1, 0, 0) y (0, 1, 0) z (0, 0, 1) at (0, 0, 0)
component "Brace_lower" placed x (1, 0, 0) y (0, 1, 0) z (0, 0, 1) at (0, 0, 0)
component "Port_round_candidate" placed x (1, 0, 0) y (0, 1, 0) z (0, 0, 1) at (0, 0, 0)
component "REF_Faital_10FE200_4ohm_DATASHEET_ENVELOPE" placed x (1, 0, 0) y (0, 1, 0) z (0, 0, 1) at (0, 0, 0)
component "REF_BC_ME10V3_DATASHEET_ENVELOPE" placed x (1, 0, 0) y (0, 1, 0) z (0, 0, 1) at (0, 0, 0)
component "REF_BC_DE10_DATASHEET_ENVELOPE" placed x (1, 0, 0) y (0, 1, 0) z (0, 0, 1) at (0, 0, 0)
component "RESERVE_amp_wiring_UNVERIFIED_no_mounting_holes" placed x (1, 0, 0) y (0, 1, 0) z (0, 0, 1) at (0, 0, 0)
equation "height = 560 mm" comment "engineering:E03_user_quality_and_assembly_priority; reversible_layout_for_wider_webs"
equation "width = 360 mm" comment "E08 internal50Ah battery, clear port channel and34L target; user allows quality/weight trade; design_candidate"
equation "depth = 340 mm" comment "E08 internal50Ah battery, clear port channel and34L target; user allows quality/weight trade; design_candidate"
equation "wall = 12 mm" comment "report:p12; design_candidate"
equation "lf_outer = 256.8 mm" comment "S31; design_candidate"
equation "lf_cutout = 233.3 mm" comment "S31; design_candidate"
equation "lf_depth = 102 mm" comment "S31; design_candidate"
equation "lf_flange = 8 mm" comment "S31; design_candidate"
equation "lf_pcd = 243.8 mm" comment "S31; design_candidate"
equation "lf_magnet_d = 115.3 mm" comment "S31:drawing_4; design_candidate"
equation "lf_magnet_depth = 34.7 mm" comment "S31:drawing_4; design_candidate"
equation "lf_basket_d = 231.8 mm" comment "S31:drawing_4; design_candidate"
equation "lf_hole_d = 5.7 mm" comment "S31:drawing_4; design_candidate"
equation "horn_width = 130.5 mm" comment "S50; design_candidate"
equation "horn_depth = 90 mm" comment "S50; design_candidate"
equation "horn_cutout = 104 mm" comment "S50:cutout_shape_to_verify; design_candidate"
equation "horn_throat = 25 mm" comment "S50; design_candidate"
equation "horn_flange = 5.5 mm" comment "S50:drawing_me10v3; manufacturer_dimension"
equation "hf_diameter = 90 mm" comment "S48; design_candidate"
equation "hf_depth = 53 mm" comment "S48; design_candidate"
equation "lf_y = 260 mm" comment "engineering:E03_user_quality_and_assembly_priority; reversible_layout_for_wider_webs"
equation "horn_y = 470 mm" comment "engineering:E03_user_quality_and_assembly_priority; reversible_layout_for_wider_webs"
equation "port_y = 82 mm" comment "E08 internal50Ah battery, clear port channel and34L target; user allows quality/weight trade; design_candidate"